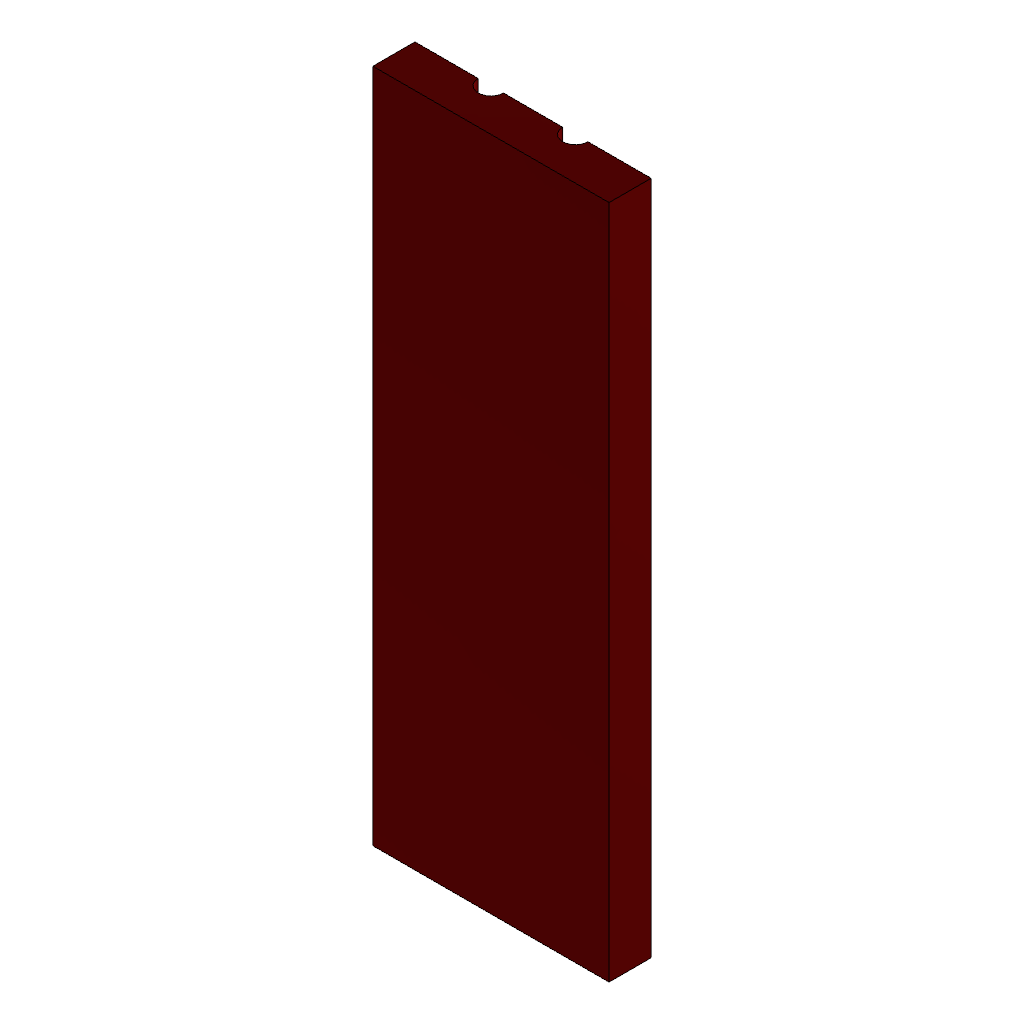
Jumper casing - 5 mm pitch - glue halves_1 (Autodesk Fusion 360 design; units mm, degrees)
part number: 2026-10-24-14-40-58-483
Autodesk Fusion 360 part; units mm, degrees
sketch "01 - centered rectangular envelope" plane through (0, 0, 0) normal (0, 0, 1) x (1, 0, 0)
  line L0 (-7, -2.5) -> (7, -2.5)
  line L1 (7, -2.5) -> (7, 2.5)
  line L2 (7, 2.5) -> (-7, 2.5)
  line L3 (-7, 2.5) -> (-7, -2.5)
  dimension "d13" = 14
  dimension "d14" = 5
  dimension "d15" = 7
  dimension "d16" = 2.5
  measures "d13" horizontal distance of L0.start L0.end
  measures "d14" vertical distance of L0.end L1.end
  measures "d15" horizontal distance of origin L0.start
  measures "d16" vertical distance of origin L0.start
extrude "02 - full casing envelope" add sketch "01 - centered rectangular envelope" along normal blind 40 makes body 1
ref_plane "WorkPlane1" through (0, 0, 0) normal (0, 0, 1) x (1, 0, 0)
sketch "03 - pin exits - paired bores" plane through (0, 0, 0) normal (0, 0, 1) x (1, 0, 0)
  circle A0 centre (-2.5, 0) radius 0.4
  circle A1 centre (2.5, 0) radius 0.4
  dimension "d21" = 2.5
  dimension "d22" = 0.8
  dimension "d23" = 2.5
  dimension "d24" = 0.8
  constraint horizontal origin A0.centre
  constraint horizontal origin A1.centre
  measures "d21" horizontal distance of origin A0.centre
  measures "d22" diameter of A0
  measures "d23" horizontal distance of origin A1.centre
  measures "d24" diameter of A1
extrude "03 - pin exits" cut sketch "03 - pin exits - paired bores" along normal blind 1 bodies 1
ref_plane "WorkPlane2" through (0, 0, 1) normal (0, 0, 1) x (1, 0, 0)
sketch "04 - connector middle seats - paired bores" plane through (0, 0, 1) normal (0, 0, 1) x (1, 0, 0)
  circle A0 centre (-2.5, 0) radius 1.5
  circle A1 centre (2.5, 0) radius 1.5
  dimension "d29" = 2.5
  dimension "d30" = 3
  dimension "d31" = 2.5
  dimension "d32" = 3
  constraint horizontal origin A0.centre
  constraint horizontal origin A1.centre
  measures "d29" horizontal distance of origin A0.centre
  measures "d30" diameter of A0
  measures "d31" horizontal distance of origin A1.centre
  measures "d32" diameter of A1
extrude "04 - connector middle seats" cut sketch "04 - connector middle seats - paired bores" along normal blind 7.9 bodies 1
ref_plane "WorkPlane3" through (0, 0, 8.9) normal (0, 0, 1) x (1, 0, 0)
sketch "05 - connector collar seats - paired bores" plane through (0, 0, 8.9) normal (0, 0, 1) x (1, 0, 0)
  circle A0 centre (-2.5, 0) radius 1.85
  circle A1 centre (2.5, 0) radius 1.85
  dimension "d37" = 2.5
  dimension "d38" = 3.7
  dimension "d39" = 2.5
  dimension "d40" = 3.7
  constraint horizontal origin A0.centre
  constraint horizontal origin A1.centre
  measures "d37" horizontal distance of origin A0.centre
  measures "d38" diameter of A0
  measures "d39" horizontal distance of origin A1.centre
  measures "d40" diameter of A1
extrude "05 - connector collar seats" cut sketch "05 - connector collar seats - paired bores" along normal blind 2 bodies 1
ref_plane "WorkPlane4" through (0, 0, 10.9) normal (0, 0, 1) x (1, 0, 0)
sketch "06 - cable passages - paired bores" plane through (0, 0, 10.9) normal (0, 0, 1) x (1, 0, 0)
  circle A0 centre (-2.5, 0) radius 0.75
  circle A1 centre (2.5, 0) radius 0.75
  dimension "d45" = 2.5
  dimension "d46" = 1.5
  dimension "d47" = 2.5
  dimension "d48" = 1.5
  constraint horizontal origin A0.centre
  constraint horizontal origin A1.centre
  measures "d45" horizontal distance of origin A0.centre
  measures "d46" diameter of A0
  measures "d47" horizontal distance of origin A1.centre
  measures "d48" diameter of A1
extrude "06 - cable passages" cut sketch "06 - cable passages - paired bores" along normal blind 29.1 bodies 1
split "07 - split through both cable axes for glue assembly" by plane through (0, 0, 0) normal (0, 1, 0) bodies 1 makes body 2 at (2.3333, 2.5, 13.3333)
hidden bodies 2
equation "case_width = 14 mm" comment "Overall width; leaves 2.65 mm outside the largest bores."
equation "case_height = 40 mm" comment "Overall length along the cables."
equation "case_thickness = 5 mm" comment "Assembled thickness; each half is 2.5 mm."
equation "pin_pitch = 5 mm" comment "Distance between both cable/pin axes."
equation "housing_length = 9.9 mm" comment "Measured total plastic connector length."
equation "housing_diameter = 2.8 mm" comment "Measured middle housing diameter."
equation "collar_diameter = 3.5 mm" comment "Measured maximum housing diameter."
equation "collar_length = 2 mm" comment "ASSUMPTION: axial length of the thickest section; measure before printing."
equation "cable_diameter = 1.3 mm" comment "Measured cable diameter."
equation "pin_diameter = 0.6 mm" comment "Measured pin diameter."
equation "diametral_clearance = 0.2 mm" comment "Total diameter allowance, equivalent to 0.1 mm on each side."
equation "tip_shoulder = 1 mm" comment "Plastic below the housing; reduces exposed pin length by 1 mm."
equation "d13 = case_width"
equation "d14 = case_thickness"
equation "d15 = case_width / 2"
equation "d16 = case_thickness / 2"
equation "d17 = case_height"
equation "d21 = pin_pitch / 2"
equation "d22 = pin_diameter + diametral_clearance"
equation "d23 = pin_pitch / 2"
equation "d24 = pin_diameter + diametral_clearance"
equation "d25 = tip_shoulder"
equation "d27 = tip_shoulder"
equation "d29 = pin_pitch / 2"
equation "d30 = housing_diameter + diametral_clearance"
equation "d31 = pin_pitch / 2"
equation "d32 = housing_diameter + diametral_clearance"
equation "d33 = housing_length - collar_length"
equation "d35 = tip_shoulder + housing_length - collar_length"
equation "d37 = pin_pitch / 2"
equation "d38 = collar_diameter + diametral_clearance"
equation "d39 = pin_pitch / 2"
equation "d40 = collar_diameter + diametral_clearance"
equation "d41 = collar_length"
equation "d43 = tip_shoulder + housing_length"
equation "d45 = pin_pitch / 2"
equation "d46 = cable_diameter + diametral_clearance"
equation "d47 = pin_pitch / 2"
equation "d48 = cable_diameter + diametral_clearance"
equation "d49 = case_height - tip_shoulder - housing_length"
named bodies: "Casing A - rear glue half", "Casing B - front glue half"
